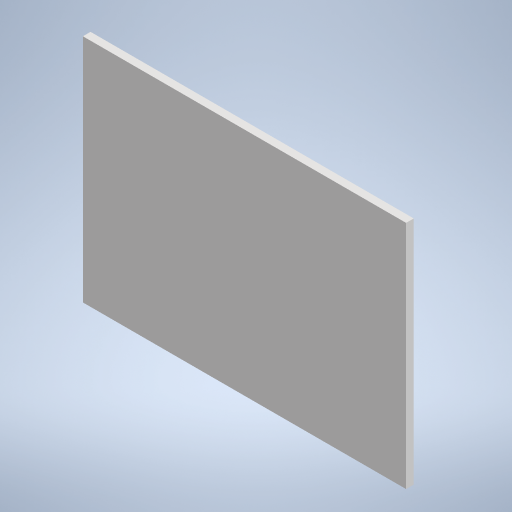
# Autodesk Inventor part: деталь крепление
Saved by Autodesk Inventor 2024.2 (Build 282272000, 272)
## iProperties
Created: 2026-09-12
Part Number: деталь крепление
Material: Типовые
Document SubType Name: Modeling
Designer: katya_notebook
Density: 1 g/cm^3
Appearance: По умолчанию
Author: katya_notebook
Autodesk Inventor part; units mm, degrees
ref_plane "YZ Plane" through (0, 0, 0) normal (1, 0, 0) x (0, 1, 0)
ref_plane "XZ Plane" through (0, 0, 0) normal (0, 1, 0) x (-1, 0, 0)
ref_plane "XY Plane" through (0, 0, 0) normal (0, 0, 1) x (1, 0, 0)
ref_plane "РабПлоскость1" through (0, 0, 0) normal (0, 0, 1) x (1, 0, 0)
sketch "Эскиз1" plane through (0, 0, 0) normal (0, 0, 1) x (1, 0, 0)
  line L0 (105.1723, 10.0688) -> (-21.0277, 10.0688)
  line L1 (-21.0277, 10.0688) -> (-21.0277, -79.9312)
  line L2 (-21.0277, -79.9312) -> (105.1723, -79.9312)
  line L3 (105.1723, -79.9312) -> (105.1723, 10.0688)
  line L4 (95.1723, -74.2312) -> (95.1723, -65.6312) projected
  line L5 (-11.0277, -74.2312) -> (-11.0277, -65.6312) projected
  circle A0 centre (58.5, -0.5) radius 1.35 projected
  circle A1 centre (58.5, -49.5) radius 1.35 projected
  circle A2 centre (0.5, -49.5) radius 1.3 projected
  circle A3 centre (0.5, -0.5) radius 1.35 projected
  point P0 (0, 0)
  point P1 (-11.0277, -69.9312)
  point P2 (95.1723, -69.9312)
  dimension "d1" = 10
  dimension "d2" = 10
  dimension "d3" = 10
  dimension "d4" = 80
  constraints: 8 end point, 2 midpoint, 2 parallel, 1 horizontal, 1 perpendicular
  measures "d1" distance from line of point (-11.028, -69.931) L1
  measures "d2" distance from line of L3 point (95.172, -69.931)
  measures "d3" distance from line of point (-11.028, -69.931) L2
  measures "d4" distance from line of L0 point (-11.028, -69.931)
extrude "Выдавливание1" add sketch "Эскиз1" along normal blind 3 contours L3 L2 L1 L0 | A0 | A1 | A2 | A3
sketch "Эскиз2" plane through (0, 0, 0) normal (0, 0, -1) x (-1, 0, 0)
  circle A0 centre (-58.5, -49.5) radius 1.35 projected
  circle A1 centre (-0.5, -49.5) radius 1.3 projected
  circle A2 centre (-0.5, -0.5) radius 1.35 projected
  circle A3 centre (-58.5, -0.5) radius 1.35 projected
  circle A4 centre (-0.5, -0.5) radius 1
  circle A5 centre (-58.5, -0.5) radius 1
  circle A6 centre (-58.5, -49.5) radius 1
  circle A7 centre (-0.5, -49.5) radius 1
  point P0 (0, 0)
  dimension "d7" = 2
  dimension "d8" = 2
  dimension "d9" = 2
  dimension "d10" = 2
  constraints: 4 centre point, 4 coincident
  measures "d7" diameter of A4
  measures "d8" diameter of A5
  measures "d9" diameter of A6
  measures "d10" diameter of A7
extrude "Выдавливание2" add sketch "Эскиз2" along normal blind 5 contours A4 | A5 | A6 | A7
sketch "Эскиз3" plane through (0, 0, 0) normal (0, 0, -1) x (-1, 0, 0)
  line L0 (10.2777, -61.6312) -> (4.7777, -61.6312) projected
  line L1 (-88.9223, -61.6312) -> (-94.4223, -61.6312) projected
  line L2 (10.8672, -61.6312) -> (4.8672, -61.6312)
  line L3 (4.8672, -61.6312) -> (4.8672, -57.6312)
  line L4 (4.8672, -57.6312) -> (10.8672, -57.6312)
  line L5 (10.8672, -57.6312) -> (10.8672, -61.6312)
  line L6 (-88.617, -61.6312) -> (-94.617, -61.6312)
  line L7 (-94.617, -61.6312) -> (-94.617, -57.6312)
  line L8 (-94.617, -57.6312) -> (-88.617, -57.6312)
  line L9 (-88.617, -57.6312) -> (-88.617, -61.6312)
  point P0 (0, 0)
  point P1 (7.8672, -61.6312)
  dimension "d13" = 4
  dimension "d14" = 6
  dimension "d15" = 4
  dimension "d16" = 6
  constraints: 16 end point, 4 parallel, 2 horizontal, 2 perpendicular, 2 point on line, 1 midpoint
  measures "d13" distance of L2.end L3.end
  measures "d14" distance of L3.end L4.end
  measures "d15" distance of L8.end L6.start
  measures "d16" distance of L7.end L8.end
extrude "Выдавливание3" add sketch "Эскиз3" along normal blind 6
sketch "Эскиз4" plane through (-10.8672, -57.6312, 0) normal (0, 1, 0) x (1, 0, 0)
  circle A0 centre (3.3396, 3.05) radius 1 projected
  circle A1 centre (102.5396, 3.05) radius 1 projected
  point P0 (10.8672, 0)
extrude "Выдавливание4" cut sketch "Эскиз4" against normal blind 6
chamfer "Фаска1" distance 2 angle 45 6 edges at (-7.8672, -57.6312, 0) (-10.8672, -59.6312, 0) (-4.8672, -59.6312, 0) (91.617, -57.6312, 0) (94.617, -59.6312, 0) (88.617, -59.6312, 0)
